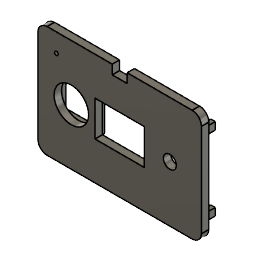
SLEEPHELPERCONFIG (Autodesk Fusion 360 archive; units mm, degrees)
design "SleepHelperFront"
part number: 2026-09-22-17-51-52-416
Autodesk Fusion 360 part; units mm, degrees
sketch "Sketch1" plane through (0, 0, 0) normal (0, 0, 1) x (1, 0, 0)
  line L0 (0, 0) -> (88, 0)
  line L1 (88, 0) -> (88, 60)
  line L2 (88, 60) -> (0, 60)
  line L3 (0, 60) -> (0, 0)
  dimension "d1" = 88
  dimension "d2" = 60
  constraint horizontal L0
  constraint vertical L1
  constraint horizontal L2
  constraint vertical L3
  constraint coincident L0.start L3.end
  measures "d1" distance of L0.start L0.end
  measures "d2" distance of L0.start L2.end
extrude "Extrude1" add sketch "Sketch1" along normal blind 4
fillet "Fillet1" radius 5 4 edges at (0, 60, 2) (88, 60, 2) (88, 0, 2) (0, 0, 2)
sketch "Sketch2" plane through (0, 0, 4) normal (0, 0, 1) x (1, 0, 0)
  arc A0 (0, 5) -> (5, 0) centre (5, 5) ccw
  line L0 (5, 0) -> (83, 0)
  arc A1 (83, 0) -> (88, 5) centre (83, 5) ccw
  line L1 (88, 5) -> (88, 55)
  arc A2 (88, 55) -> (83, 60) centre (83, 55) ccw
  line L2 (83, 60) -> (5, 60)
  arc A3 (5, 60) -> (0, 55) centre (5, 55) ccw
  line L3 (0, 55) -> (0, 5)
  line L4 (0, 30) -> (88, 30) construction
  circle A4 centre (18, 30) radius 9.25
  circle A5 centre (71, 30) radius 3.5
  line L5 (44, 60) -> (44, 0) construction
  line L6 (30.75, 20.5) -> (57.25, 20.5)
  line L7 (57.25, 20.5) -> (57.25, 39.5)
  line L8 (57.25, 39.5) -> (30.75, 39.5)
  line L9 (30.75, 39.5) -> (30.75, 20.5)
  circle A6 centre (71, 30) radius 10 construction
  line L10 (29.75, 41.5) -> (58.25, 41.5)
  line L11 (58.25, 41.5) -> (58.25, 18.5)
  line L12 (58.25, 18.5) -> (29.75, 18.5)
  line L13 (29.75, 18.5) -> (29.75, 41.5)
  line L14 (30.75, 39.5) -> (29.75, 39.5)
  line L15 (30.75, 20.5) -> (29.75, 20.5)
  dimension "d7" = 18.5
  dimension "d8" = 18
  dimension "d9" = 7
  dimension "d10" = 17
  dimension "d11" = 19
  dimension "d12" = 26.5
  dimension "d13" = 20.5
  dimension "d14" = 30.75
  dimension "d19" = 20
  dimension "d47" = 28.5
  dimension "d48" = 23
  dimension "d49" = 2
  dimension "d50" = 1
  constraint midpoint L3 L4.start
  constraint midpoint L1 L4.end
  constraint coincident L4 A4.centre
  constraint coincident L4 A5.centre
  constraint midpoint L2 L5.start
  constraint midpoint L0 L5.end
  constraint horizontal L6
  constraint vertical L7
  constraint horizontal L8
  constraint vertical L9
  constraint concentric A5 A6
  constraint horizontal L10
  constraint vertical L11
  constraint horizontal L12
  constraint vertical L13
  constraint coincident L13 L14.end
  constraint perpendicular L13 L14
  constraint coincident L13 L15.end
  constraint perpendicular L13 L15
  measures "d7" diameter of A4
  measures "d8" distance of L3 A4.centre
  measures "d9" diameter of A5
  measures "d10" distance of L1 A5.centre
  measures "d11" distance of L6.start L8.end
  measures "d12" distance of L6.start L6.end
  measures "d13" distance of L2 L8
  measures "d14" distance of L3 L9
  measures "d19" diameter of A6
  measures "d47" distance of L10.start L10.end
  measures "d48" distance of L10.start L12.end
  measures "d49" distance of L8 L10
  measures "d50" distance of L7 L11
extrude "Extrude2" cut sketch "Sketch2" against normal blind 5 contours A4 | A5 | L6 L7 L8 L9
sketch "Sketch6" plane through (0, 0, 0) normal (0, 0, -1) x (-1, 0, 0)
  line L0 (-30.75, 20.5) -> (-57.25, 20.5)
  line L1 (-57.25, 20.5) -> (-57.25, 39.5)
  line L2 (-57.25, 39.5) -> (-30.75, 39.5)
  line L3 (-30.75, 39.5) -> (-30.75, 20.5)
  circle A0 centre (-18, 30) radius 9.25
  circle A1 centre (-71, 30) radius 3.5
  arc A2 (-5, 0) -> (0, 5) centre (-5, 5) ccw
  line L4 (0, 5) -> (0, 55)
  arc A3 (0, 55) -> (-5, 60) centre (-5, 55) ccw
  line L5 (-5, 60) -> (-83, 60)
  arc A4 (-83, 60) -> (-88, 55) centre (-83, 55) ccw
  line L6 (-88, 55) -> (-88, 5)
  arc A5 (-88, 5) -> (-83, 0) centre (-83, 5) ccw
  line L7 (-83, 0) -> (-5, 0)
  line L8 (-58.25, 43.5) -> (-29.75, 43.5)
  line L9 (-29.75, 43.5) -> (-29.75, 16.5)
  line L10 (-29.75, 16.5) -> (-58.25, 16.5)
  line L11 (-58.25, 16.5) -> (-58.25, 43.5)
  line L12 (-27.75, 14.5) -> (-60.25, 14.5)
  line L13 (-60.25, 14.5) -> (-60.25, 45.5)
  line L14 (-60.25, 45.5) -> (-27.75, 45.5)
  line L15 (-27.75, 45.5) -> (-27.75, 14.5)
  dimension "d37" = 4
  dimension "d38" = 28.5
  dimension "d39" = 1
  dimension "d40" = 27
  dimension "d41" = -2
  constraint horizontal L8
  constraint vertical L9
  constraint horizontal L10
  constraint vertical L11
  measures "d37" distance of L2 L8
  measures "d38" distance of L9.end L10.end
  measures "d39" distance of L1 L11
  measures "d40" distance of L8.start L10.end
extrude "Extrude6" add sketch "Sketch6" along normal blind 3 contours L12 L13 L14 L15
sketch "Sketch7" plane through (0, 0, 0) normal (0, 0, -1) x (-1, 0, 0)
  arc A0 (-5, 0) -> (0, 5) centre (-5, 5) ccw
  line L0 (0, 5) -> (0, 55)
  arc A1 (0, 55) -> (-5, 60) centre (-5, 55) ccw
  line L1 (-5, 60) -> (-83, 60)
  arc A2 (-83, 60) -> (-88, 55) centre (-83, 55) ccw
  line L2 (-88, 55) -> (-88, 5)
  arc A3 (-88, 5) -> (-83, 0) centre (-83, 5) ccw
  line L3 (-83, 0) -> (-5, 0)
  circle A4 centre (-71, 30) radius 3.5
  circle A5 centre (-18, 30) radius 9.25
  line L4 (-27.75, 45.5) -> (-27.75, 14.5)
  line L5 (-27.75, 14.5) -> (-60.25, 14.5)
  line L6 (-60.25, 14.5) -> (-60.25, 45.5)
  line L7 (-60.25, 45.5) -> (-27.75, 45.5)
  line L8 (-28.125, 40) -> (-8.125, 40)
  line L9 (-8.125, 40) -> (-8.125, 20)
  line L10 (-8.125, 20) -> (-28.125, 20)
  line L11 (-28.125, 20) -> (-28.125, 40)
  line L12 (-6.875, 18.75) -> (-29.375, 18.75)
  line L13 (-29.375, 18.75) -> (-29.375, 41.25)
  line L14 (-29.375, 41.25) -> (-6.875, 41.25)
  line L15 (-6.875, 41.25) -> (-6.875, 18.75)
  dimension "d44" = -1.25
  dimension "d61" = 9.875
  constraint horizontal L8
  constraint vertical L9
  constraint horizontal L10
  constraint vertical L11
  measures "d61" distance of A5.centre L9
extrude "Extrude7" add sketch "Sketch7" along normal blind 3 contours L4 L8 L9 L10 L12 L14 L15 | L4 L8 L10 L11 L12 L13 L14
sketch "Sketch9" plane through (0, 0, 4) normal (0, 0, 1) x (1, 0, 0)
  line L0 (57.25, 20.5) -> (30.75, 20.5)
  line L1 (30.75, 20.5) -> (30.75, 39.5)
  line L2 (30.75, 39.5) -> (57.25, 39.5)
  line L3 (57.25, 39.5) -> (57.25, 20.5)
  circle A0 centre (18, 30) radius 9.25
  circle A1 centre (71, 30) radius 3.5
  arc A2 (0, 5) -> (5, 0) centre (5, 5) ccw
  line L4 (5, 0) -> (83, 0)
  arc A3 (83, 0) -> (88, 5) centre (83, 5) ccw
  line L5 (88, 5) -> (88, 55)
  arc A4 (88, 55) -> (83, 60) centre (83, 55) ccw
  line L6 (83, 60) -> (5, 60)
  arc A5 (5, 60) -> (0, 55) centre (5, 55) ccw
  line L7 (0, 55) -> (0, 5)
  circle A6 centre (10, 50) radius 1
  dimension "d54" = 2
  measures "d54" diameter of A6
extrude "Extrude9" cut sketch "Sketch9" against normal blind 21 contours A6
sketch "Sketch10" plane through (0, 60, 0) normal (0, 1, 0) x (-1, 0, 0)
  line L0 (-83, 4) -> (-83, 0)
  line L1 (-83, 0) -> (-5, 0)
  line L2 (-5, 0) -> (-5, 4)
  line L3 (-5, 4) -> (-83, 4)
  line L4 (-40, 0) -> (-48, 0)
  line L5 (-48, 0) -> (-48, 4)
  line L6 (-48, 4) -> (-40, 4)
  line L7 (-40, 4) -> (-40, 0)
  dimension "d57" = 8
  dimension "d58" = 35
  constraint horizontal L4
  constraint vertical L5
  constraint horizontal L6
  constraint vertical L7
  constraint coincident L1 L4.start
  measures "d57" distance of L4.start L4.end
  measures "d58" distance of L2 L7
extrude "Extrude10" cut sketch "Sketch10" against normal blind 5 contours L1 L3 L4 L5 L6 L7
sketch "Sketch11" plane through (0, 0, -3) normal (0, 0, -1) x (-1, 0, 0)
  line L0 (-27.75, 20) -> (-27.75, 40)
  line L1 (-27.75, 40) -> (-8.125, 40)
  line L2 (-8.125, 40) -> (-8.125, 20)
  line L3 (-8.125, 20) -> (-27.75, 20)
  line L4 (-29.75, 16.5) -> (-58.25, 16.5)
  line L5 (-58.25, 16.5) -> (-58.25, 43.5)
  line L6 (-58.25, 43.5) -> (-29.75, 43.5)
  line L7 (-29.75, 43.5) -> (-29.75, 16.5)
  line L8 (-27.75, 18.75) -> (-6.875, 18.75)
  line L9 (-6.875, 18.75) -> (-6.875, 41.25)
  line L10 (-6.875, 41.25) -> (-27.75, 41.25)
  line L11 (-27.75, 41.25) -> (-27.75, 45.5)
  line L12 (-27.75, 45.5) -> (-60.25, 45.5)
  line L13 (-60.25, 45.5) -> (-60.25, 14.5)
  line L14 (-60.25, 14.5) -> (-27.75, 14.5)
  line L15 (-27.75, 14.5) -> (-27.75, 18.75)
  line L16 (-29.75, 16.5) -> (-27.75, 16.5)
  line L17 (-27.75, 18.75) -> (-29.75, 18.75)
  line L18 (-29.75, 18.75) -> (-29.75, 16.5)
  line L19 (-27.75, 16.5) -> (-27.75, 18.75)
  line L20 (-29.75, 43.5) -> (-27.75, 43.5)
  line L21 (-27.75, 43.5) -> (-27.75, 41.25)
  line L22 (-27.75, 41.25) -> (-29.75, 41.25)
  line L23 (-29.75, 41.25) -> (-29.75, 43.5)
  constraint coincident L4.start L7.end
  constraint coincident L15 L16.end
  constraint perpendicular L15 L16
  constraint coincident L8.start L15.end
  constraint coincident L7 L17.end
  constraint perpendicular L7 L17
  constraint horizontal L20
  constraint vertical L21
  constraint horizontal L22
  constraint vertical L23
  constraint coincident L10.end L11.start
  constraint coincident L6.end L7.start
extrude "Extrude11" cut sketch "Sketch11" against normal blind 3 contours L7 L15 L16 L17 L18 L19 | L7 L11 L20 L21 L22 L23
sketch "Sketch12" plane through (0, 0, -3) normal (0, 0, -1) x (-1, 0, 0)
  line L0 (-29.75, 18.75) -> (-6.875, 18.75)
  line L1 (-6.875, 18.75) -> (-6.875, 41.25)
  line L2 (-6.875, 41.25) -> (-29.75, 41.25)
  line L3 (-29.75, 41.25) -> (-29.75, 18.75)
  line L4 (-27.75, 20) -> (-27.75, 40)
  line L5 (-27.75, 40) -> (-8.125, 40)
  line L6 (-8.125, 40) -> (-8.125, 20)
  line L7 (-8.125, 20) -> (-27.75, 20)
  line L8 (-29, 41.25) -> (-29, 18.75)
  dimension "d64" = 1.25
  constraint coincident L2 L8.start
  constraint coincident L0 L8.end
  constraint perpendicular L0 L8
  measures "d64" distance of L4 L8
extrude "Extrude12" cut sketch "Sketch12" against normal blind 3 contours L0 L2 L3 L8
sketch "Sketch13" plane through (0, 0, 0) normal (0, 0, -1) x (-1, 0, 0)
  line L0 (-29, 41.25) -> (-6.875, 41.25)
  line L1 (-6.875, 41.25) -> (-6.875, 18.75)
  line L2 (-6.875, 18.75) -> (-29, 18.75)
  line L3 (-29, 18.75) -> (-29, 41.25)
  line L4 (-30.75, 20.5) -> (-57.25, 20.5)
  line L5 (-57.25, 20.5) -> (-57.25, 39.5)
  line L6 (-57.25, 39.5) -> (-30.75, 39.5)
  line L7 (-30.75, 39.5) -> (-30.75, 20.5)
  line L8 (-48, 55) -> (-48, 60)
  line L9 (-48, 60) -> (-83, 60)
  arc A0 (-83, 60) -> (-88, 55) centre (-83, 55) ccw
  line L10 (-88, 55) -> (-88, 5)
  arc A1 (-88, 5) -> (-83, 0) centre (-83, 5) ccw
  line L11 (-83, 0) -> (-5, 0)
  arc A2 (-5, 0) -> (0, 5) centre (-5, 5) ccw
  line L12 (0, 5) -> (0, 55)
  arc A3 (0, 55) -> (-5, 60) centre (-5, 55) ccw
  line L13 (-5, 60) -> (-40, 60)
  line L14 (-40, 60) -> (-40, 55)
  line L15 (-40, 55) -> (-48, 55)
  circle A4 centre (-10, 50) radius 1
  line L16 (-58.25, 16.5) -> (-27.75, 16.5)
  line L17 (-27.75, 16.5) -> (-27.75, 14.5)
  line L18 (-27.75, 14.5) -> (-60.25, 14.5)
  line L19 (-60.25, 14.5) -> (-60.25, 45.5)
  line L20 (-60.25, 45.5) -> (-27.75, 45.5)
  line L21 (-27.75, 45.5) -> (-27.75, 43.5)
  line L22 (-27.75, 43.5) -> (-58.25, 43.5)
  line L23 (-58.25, 43.5) -> (-58.25, 16.5)
  circle A5 centre (-71, 30) radius 3.5
  line L24 (-86.5, 52) -> (-84, 52)
  line L25 (-84, 52) -> (-84, 48)
  line L26 (-84, 48) -> (-86.5, 48)
  line L27 (-86.5, 48) -> (-86.5, 52)
  line L28 (-86.5, 12) -> (-84, 12)
  line L29 (-84, 12) -> (-84, 8)
  line L30 (-84, 8) -> (-86.5, 8)
  line L31 (-86.5, 8) -> (-86.5, 12)
  line L32 (-44, 0) -> (-44, 55) construction
  line L33 (-1.5, 52) -> (-4, 52)
  line L34 (-4, 52) -> (-4, 48)
  line L35 (-4, 48) -> (-1.5, 48)
  line L36 (-1.5, 48) -> (-1.5, 52)
  line L37 (-4, 12) -> (-4, 8)
  line L38 (-1.5, 12) -> (-4, 12)
  line L39 (-1.5, 8) -> (-1.5, 12)
  line L40 (-4, 8) -> (-1.5, 8)
  dimension "d67" = 2.5
  dimension "d68" = 4
  dimension "d69" = 2.5
  dimension "d70" = 4
  dimension "d71" = 1.5
  dimension "d72" = 8
  dimension "d73" = 1.5
  dimension "d74" = 8
  constraint horizontal L24
  constraint vertical L25
  constraint horizontal L26
  constraint vertical L27
  constraint horizontal L28
  constraint vertical L29
  constraint horizontal L30
  constraint vertical L31
  constraint midpoint L11 L32.start
  constraint midpoint L15 L32.end
  constraint symmetric L24.start L32 L33.start
  constraint symmetric L24.end L32 L33.end
  constraint symmetric L25.end L32 L34.end
  constraint symmetric L26.end L32 L35.end
  constraint symmetric L28.start L32 L38.start
  constraint symmetric L28.end L32 L37.start
  constraint symmetric L29.end L32 L37.end
  constraint symmetric L30.end L32 L39.start
  measures "d67" distance of L24.start L24.end
  measures "d68" distance of L24.start L26.end
  measures "d69" distance of L28.start L28.end
  measures "d70" distance of L28.start L30.end
  measures "d71" distance of L10 L27
  measures "d72" distance of L9.end L24
  measures "d73" distance of L10 L28.start
  measures "d74" vertical distance of A1.end L29.end
extrude "Extrude13" add sketch "Sketch13" along normal blind 5 contours L24 L25 L26 L27 | L28 L29 L30 L31 | L33 L34 L35 L36 | L37 L38 L39 L40
equation "d12 = 27.5 mm - 1 mm"
equation "d13 = ( ( 60 - 19 ) / 2 ) * 1 mm"
equation "d14 = ( ( ( 88 - 27.5 ) / 2 ) * 1 mm ) + 0.5 * 1 mm"
equation "d48 = 19 mm + 4 mm"
equation "d61 = ( 19.75 / 2 ) * 1 mm"

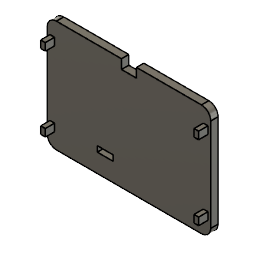
design "SleepHelperBack"
part number: 2026-09-24-13-16-22-651
Autodesk Fusion 360 part; units mm, degrees
sketch "Sketch1" plane through (0, 0, 0) normal (0, 0, 1) x (1, 0, 0)
  line L0 (0, 0) -> (-88, 0)
  line L1 (-88, 0) -> (-88, 60)
  line L2 (-88, 60) -> (0, 60)
  line L3 (0, 60) -> (0, 0)
  dimension "d1" = 88
  dimension "d2" = 60
  constraint horizontal L0
  constraint vertical L1
  constraint horizontal L2
  constraint vertical L3
  constraint coincident L0.start L3.end
  measures "d1" distance of L0.start L0.end
  measures "d2" distance of L0.start L2.end
extrude "Extrude1" add sketch "Sketch1" along normal blind 4
fillet "Fillet1" radius 5 4 edges at (0, 60, 2) (-88, 60, 2) (0, 0, 2) (-88, 0, 2)
sketch "Sketch2" plane through (0, 0, 0) normal (0, 0, -1) x (-1, 0, 0)
  arc A0 (83, 0) -> (88, 5) centre (83, 5) ccw
  line L0 (88, 5) -> (88, 55)
  arc A1 (88, 55) -> (83, 60) centre (83, 55) ccw
  line L1 (83, 60) -> (5, 60)
  arc A2 (5, 60) -> (0, 55) centre (5, 55) ccw
  line L2 (0, 55) -> (0, 5)
  arc A3 (0, 5) -> (5, 0) centre (5, 5) ccw
  line L3 (5, 0) -> (83, 0)
  line L4 (83, 60) -> (83, 0) construction
  line L5 (52.5, 13) -> (61, 13)
  line L6 (61, 13) -> (61, 10)
  line L7 (61, 10) -> (52.5, 10)
  line L8 (52.5, 10) -> (52.5, 13)
  dimension "d7" = 8.5
  dimension "d8" = 3
  dimension "d9" = 22
  dimension "d10" = 10
  constraint coincident A1.end L1.start
  constraint coincident A0.start L3.end
  constraint horizontal L5
  constraint vertical L6
  constraint horizontal L7
  constraint vertical L8
  measures "d7" distance of L5.start L5.end
  measures "d8" distance of L5.start L7.end
  measures "d9" distance of L4 L6
  measures "d10" distance of L3 L7
extrude "Extrude2" cut sketch "Sketch2" against normal blind 35 contours L5 L6 L7 L8
sketch "Sketch4" plane through (0, 60, 0) normal (0, 1, 0) x (-1, 0, 0)
  line L0 (83, 0) -> (83, 4)
  line L1 (83, 4) -> (5, 4)
  line L2 (5, 4) -> (5, 0)
  line L3 (5, 0) -> (83, 0)
  line L4 (40, 4) -> (48, 4)
  line L5 (48, 4) -> (48, 0)
  line L6 (48, 0) -> (40, 0)
  line L7 (40, 0) -> (40, 4)
  dimension "d18" = 8
  dimension "d19" = 4
  dimension "d20" = 35
  constraint horizontal L4
  constraint vertical L5
  constraint horizontal L6
  constraint vertical L7
  constraint coincident L1 L4.start
  measures "d18" distance of L4.start L4.end
  measures "d19" distance of L4.start L6.end
  measures "d20" distance of L2.end L7
extrude "Extrude4" cut sketch "Sketch4" against normal blind 5 contours L1 L3 L4 L5 L6 L7
sketch "Sketch5" plane through (0, 0, 4) normal (0, 0, 1) x (1, 0, 0)
  line L0 (-40, 60) -> (-40, 55)
  line L1 (-40, 55) -> (-48, 55)
  line L2 (-48, 55) -> (-48, 60)
  line L3 (-48, 60) -> (-83, 60)
  arc A0 (-83, 60) -> (-88, 55) centre (-83, 55) ccw
  line L4 (-88, 55) -> (-88, 5)
  arc A1 (-88, 5) -> (-83, 0) centre (-83, 5) ccw
  line L5 (-83, 0) -> (-5, 0)
  arc A2 (-5, 0) -> (0, 5) centre (-5, 5) ccw
  line L6 (0, 5) -> (0, 55)
  arc A3 (0, 55) -> (-5, 60) centre (-5, 55) ccw
  line L7 (-5, 60) -> (-40, 60)
  line L8 (-61, 10) -> (-61, 13)
  line L9 (-61, 13) -> (-52.5, 13)
  line L10 (-52.5, 13) -> (-52.5, 10)
  line L11 (-52.5, 10) -> (-61, 10)
  line L12 (-86.5, 52) -> (-84, 52)
  line L13 (-84, 52) -> (-84, 48)
  line L14 (-84, 48) -> (-86.5, 48)
  line L15 (-86.5, 48) -> (-86.5, 52)
  line L16 (-86.5, 12) -> (-84, 12)
  line L17 (-84, 12) -> (-84, 8)
  line L18 (-84, 8) -> (-86.5, 8)
  line L19 (-86.5, 8) -> (-86.5, 12)
  line L20 (-44, 55) -> (-44, 0) construction
  line L21 (-4, 52) -> (-4, 48)
  line L22 (-4, 48) -> (-1.5, 48)
  line L23 (-1.5, 48) -> (-1.5, 52)
  line L24 (-1.5, 52) -> (-4, 52)
  line L25 (-1.5, 12) -> (-4, 12)
  line L26 (-1.5, 8) -> (-1.5, 12)
  line L27 (-4, 8) -> (-1.5, 8)
  line L28 (-4, 12) -> (-4, 8)
  dimension "d23" = 2.5
  dimension "d24" = 4
  dimension "d25" = 1.5
  dimension "d26" = 8
  dimension "d27" = 1.5
  dimension "d28" = 8
  dimension "d31" = 4
  dimension "d32" = 2.5
  constraint horizontal L12
  constraint vertical L13
  constraint horizontal L14
  constraint vertical L15
  constraint horizontal L16
  constraint vertical L17
  constraint horizontal L18
  constraint vertical L19
  constraint midpoint L1 L20.start
  constraint midpoint L5 L20.end
  constraint symmetric L12.start L20 L23.end
  constraint symmetric L12.end L20 L21.start
  constraint symmetric L13.end L20 L21.end
  constraint symmetric L14.end L20 L22.end
  constraint symmetric L16.start L20 L25.start
  constraint symmetric L16.end L20 L25.end
  constraint symmetric L17.end L20 L27.start
  constraint symmetric L18.end L20 L26.start
  measures "d23" distance of L12.start L12.end
  measures "d24" distance of L12.start L14.end
  measures "d25" distance of L4 L15
  measures "d26" vertical distance of L3.end L12.end
  measures "d27" distance of L4 L19
  measures "d28" vertical distance of A1.end L17.end
  measures "d31" distance of L16.end L17.end
  measures "d32" distance of L17.end L18.end
extrude "Extrude5" add sketch "Sketch5" along normal blind 5 contours L12 L13 L14 L15 | L16 L17 L18 L19 | L21 L22 L23 L24 | L25 L26 L27 L28

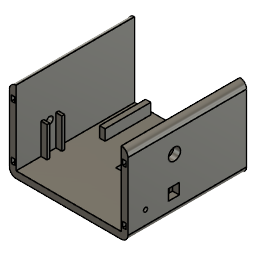
design "SidePieceSleepHelper"
part number: 2026-09-24-13-18-35-575
Autodesk Fusion 360 part; units mm, degrees
sketch "Sketch1" plane through (0, 0, 0) normal (0, 0, 1) x (1, 0, 0)
  line L0 (0, 0) -> (88, 0)
  line L1 (88, 0) -> (88, 60)
  line L2 (88, 60) -> (0, 60)
  line L3 (0, 60) -> (0, 0)
  dimension "d11" = 88
  dimension "d12" = 60
  constraint horizontal L0
  constraint vertical L1
  constraint horizontal L2
  constraint vertical L3
  constraint coincident L0.start L3.end
  measures "d11" distance of L0.start L0.end
  measures "d12" distance of L0.start L2.end
extrude "Extrude2" add sketch "Sketch1" along normal blind 88
fillet "Fillet2" radius 5 4 edges at (88, 60, 44) (0, 60, 44) (88, 0, 44) (0, 0, 44)
sketch "Sketch2" plane through (0, 0, 88) normal (0, 0, 1) x (1, 0, 0)
  arc A0 (0, 5) -> (5, 0) centre (5, 5) ccw
  line L0 (5, 0) -> (83, 0)
  arc A1 (83, 0) -> (88, 5) centre (83, 5) ccw
  line L1 (88, 5) -> (88, 55)
  arc A2 (88, 55) -> (83, 60) centre (83, 55) ccw
  line L2 (83, 60) -> (5, 60)
  arc A3 (5, 60) -> (0, 55) centre (5, 55) ccw
  line L3 (0, 55) -> (0, 5)
  line L4 (5, 55) -> (83, 55)
  line L5 (83, 55) -> (83, 5)
  line L6 (83, 5) -> (5, 5)
  line L7 (5, 5) -> (5, 55)
  constraint horizontal L4
  constraint vertical L5
  constraint horizontal L6
  constraint vertical L7
  constraint coincident A1.centre L5.end
  constraint coincident A3.centre L4.start
extrude "Extrude3" cut sketch "Sketch2" against normal blind 145 contours L4 L5 L6 L7
sketch "Sketch3" plane through (0, 0, 88) normal (0, 0, 1) x (1, 0, 0)
  line L0 (83, 55) -> (83, 5)
  line L1 (83, 5) -> (5, 5)
  line L2 (5, 5) -> (5, 55)
  line L3 (5, 55) -> (83, 55)
  arc A0 (0, 5) -> (5, 0) centre (5, 5) ccw
  line L4 (5, 0) -> (83, 0)
  arc A1 (83, 0) -> (88, 5) centre (83, 5) ccw
  line L5 (88, 5) -> (88, 55)
  arc A2 (88, 55) -> (83, 60) centre (83, 55) ccw
  line L6 (83, 60) -> (5, 60)
  arc A3 (5, 60) -> (0, 55) centre (5, 55) ccw
  line L7 (0, 55) -> (0, 5)
  line L8 (5, 60) -> (83, 60)
  line L9 (83, 60) -> (83, 55)
  line L10 (83, 55) -> (5, 55)
  line L11 (5, 55) -> (5, 60)
  constraint horizontal L8
  constraint vertical L9
  constraint horizontal L10
  constraint vertical L11
  constraint coincident L0.start L3.end
  constraint coincident L6.end A3.start
extrude "Extrude4" cut sketch "Sketch3" against normal blind 130 contours L3 L6 L8 L9 L10 L11
sketch "Sketch4" plane through (0, 0, 0) normal (-1, 0, 0) x (0, 0, 1)
  line L0 (0, 5) -> (88, 5)
  line L1 (88, 5) -> (88, 55)
  line L2 (88, 55) -> (0, 55)
  line L3 (0, 55) -> (0, 5)
  circle A0 centre (63, 25) radius 2.5
  dimension "d21" = 25
  dimension "d22" = 20
  dimension "d25" = 5
  measures "d21" distance of L1 A0.centre
  measures "d22" distance of L0 A0.centre
  measures "d25" diameter of A0
extrude "Extrude5" cut sketch "Sketch4" against normal blind 12 contours A0
sketch "Sketch5" plane through (88, 0, 0) normal (1, 0, 0) x (0, 0, -1)
  line L0 (-88, 5) -> (0, 5)
  line L1 (0, 5) -> (0, 55)
  line L2 (0, 55) -> (-88, 55)
  line L3 (-88, 55) -> (-88, 5)
  line L4 (-58, 20) -> (-50, 20)
  line L5 (-50, 20) -> (-50, 12)
  line L6 (-50, 12) -> (-58, 12)
  line L7 (-58, 12) -> (-58, 20)
  dimension "d26" = 8
  dimension "d27" = 8
  dimension "d28" = 7
  dimension "d29" = 30
  constraint horizontal L4
  constraint vertical L5
  constraint horizontal L6
  constraint vertical L7
  measures "d26" distance of L4.start L4.end
  measures "d27" distance of L4.start L6.end
  measures "d28" distance of L0 L6
  measures "d29" distance of L3 L7
extrude "Extrude6" cut sketch "Sketch5" against normal blind 35 contours L4 L5 L6 L7
sketch "Sketch6" plane through (0, 5, 0) normal (0, 1, 0) x (-1, 0, 0)
  line L0 (-83, 0) -> (-5, 0)
  line L1 (-5, 0) -> (-5, 88)
  line L2 (-5, 88) -> (-83, 88)
  line L3 (-83, 88) -> (-83, 0)
  line L4 (-15, 2) -> (-19, 2)
  line L5 (-19, 2) -> (-19, 36)
  line L6 (-19, 36) -> (-15, 36)
  line L7 (-15, 36) -> (-15, 2)
  line L8 (-41, 2) -> (-44, 2)
  line L9 (-44, 2) -> (-44, 36)
  line L10 (-44, 36) -> (-41, 36)
  line L11 (-41, 36) -> (-41, 2)
  dimension "d36" = 34
  dimension "d37" = 22
  dimension "d38" = 10
  dimension "d41" = 2
  constraint horizontal L4
  constraint vertical L5
  constraint horizontal L6
  constraint vertical L7
  constraint horizontal L8
  constraint vertical L9
  constraint horizontal L10
  constraint vertical L11
  measures "d36" distance of L4.start L6.end
  measures "d37" distance of L5 L11
  measures "d38" distance of L1 L7
  measures "d41" distance of L0 L4
extrude "Extrude7" add sketch "Sketch6" along normal blind 8 contours L4 L5 L6 L7 | L8 L9 L10 L11
sketch "Sketch7" plane through (88, 0, 0) normal (1, 0, 0) x (0, 0, -1)
  line L0 (-50, 20) -> (-50, 12)
  line L1 (-50, 12) -> (-58, 12)
  line L2 (-58, 12) -> (-58, 20)
  line L3 (-58, 20) -> (-50, 20)
  line L4 (-88, 5) -> (0, 5)
  line L5 (0, 5) -> (0, 55)
  line L6 (0, 55) -> (-88, 55)
  line L7 (-88, 55) -> (-88, 5)
  circle A0 centre (-75, 15) radius 1.5
  dimension "d42" = 3
  measures "d42" diameter of A0
extrude "Extrude8" cut sketch "Sketch7" against normal blind 41 contours A0
sketch "Sketch8" plane through (83, 0, 0) normal (-1, 0, 0) x (0, 0, 1)
  circle A0 centre (75, 15) radius 1.5
  line L0 (50, 12) -> (50, 20)
  line L1 (50, 20) -> (58, 20)
  line L2 (58, 20) -> (58, 12)
  line L3 (58, 12) -> (50, 12)
  line L4 (0, 60) -> (0, 5)
  line L5 (0, 5) -> (88, 5)
  line L6 (88, 5) -> (88, 60)
  line L7 (88, 60) -> (0, 60)
  line L8 (59.5, 20) -> (61.5, 20)
  line L9 (61.5, 20) -> (61.5, 12)
  line L10 (59.5, 12) -> (59.5, 20)
  line L11 (48.5, 20) -> (46.5, 20)
  line L12 (46.5, 20) -> (46.5, 12)
  line L13 (48.5, 12) -> (48.5, 20)
  line L14 (59.5, 12) -> (59.5, 5)
  line L15 (61.5, 12) -> (61.5, 5)
  line L16 (46.5, 12) -> (46.5, 5)
  line L17 (48.5, 12) -> (48.5, 5)
  line L18 (46.5, 5) -> (48.5, 5)
  line L19 (59.5, 5) -> (61.5, 5)
  dimension "d45" = 2
  dimension "d46" = 2
  dimension "d47" = 8
  dimension "d48" = 1.5
  dimension "d49" = 1.5
  constraint horizontal L8
  constraint vertical L9
  constraint vertical L10
  constraint horizontal L11
  constraint vertical L12
  constraint vertical L13
  constraint coincident L5 L14.end
  constraint perpendicular L5 L14
  constraint coincident L5 L15.end
  constraint perpendicular L5 L15
  constraint coincident L5 L16.end
  constraint perpendicular L5 L16
  constraint coincident L5 L17.end
  constraint perpendicular L5 L17
  measures "d45" distance of L8.start L8.end
  measures "d46" distance of L11.start L11.end
  measures "d47" distance of L11.start L13.start
  measures "d48" distance of L0 L13
  measures "d49" distance of L2.end L10.start
extrude "Extrude9" add sketch "Sketch8" along normal blind 4 contours L5 L11 L12 L13 L16 L17 L18 | L5 L8 L9 L10 L14 L15 L19
sketch "Sketch9" plane through (5, 0, 0) normal (1, 0, 0) x (0, 0, -1)
  circle A0 centre (-63, 25) radius 2.5
  line L0 (0, 5) -> (0, 60)
  line L1 (0, 60) -> (-88, 60)
  line L2 (-88, 60) -> (-88, 5)
  line L3 (-88, 5) -> (0, 5)
  line L4 (-69.5, 27.6793) -> (-67.5, 27.6793)
  line L5 (-67.5, 27.6793) -> (-67.5, 13.6793)
  line L6 (-69.5, 13.6793) -> (-69.5, 27.6793)
  line L7 (-58.5, 27.6793) -> (-56.5, 27.6793)
  line L8 (-56.5, 27.6793) -> (-56.5, 13.6793)
  line L9 (-58.5, 13.6793) -> (-58.5, 27.6793)
  line L10 (-69.5, 13.6793) -> (-69.5, 5)
  line L11 (-67.5, 13.6793) -> (-67.5, 5)
  line L12 (-69.5, 5) -> (-67.5, 5)
  line L13 (-58.5, 13.6793) -> (-58.5, 5)
  line L14 (-56.5, 13.6793) -> (-56.5, 5)
  line L15 (-58.5, 5) -> (-56.5, 5)
  dimension "d52" = 2
  dimension "d53" = 14
  dimension "d54" = 2
  dimension "d55" = 4.5
  dimension "d56" = 4.5
  constraint horizontal L4
  constraint vertical L5
  constraint vertical L6
  constraint horizontal L7
  constraint vertical L8
  constraint vertical L9
  constraint coincident L3 L10.end
  constraint perpendicular L3 L10
  constraint coincident L3 L11.end
  constraint perpendicular L3 L11
  constraint coincident L3 L13.end
  constraint perpendicular L3 L13
  constraint coincident L3 L14.end
  constraint perpendicular L3 L14
  measures "d52" distance of L4.start L4.end
  measures "d53" distance of L4.start L6.start
  measures "d54" distance of L7.start L7.end
  measures "d55" distance of A0.centre L9
  measures "d56" distance of A0.centre L5
extrude "Extrude10" add sketch "Sketch9" along normal blind 4.5 contours L3 L7 L8 L9 L13 L14 L15 | L3 L4 L5 L6 L10 L11 L12
sketch "Sketch10" plane through (0, 5, 0) normal (0, 1, 0) x (-1, 0, 0)
  line L0 (-41, 36) -> (-41, 2)
  line L1 (-41, 2) -> (-44, 2)
  line L2 (-44, 2) -> (-44, 36)
  line L3 (-44, 36) -> (-41, 36)
  line L4 (-15, 36) -> (-15, 2)
  line L5 (-15, 2) -> (-19, 2)
  line L6 (-19, 2) -> (-19, 36)
  line L7 (-19, 36) -> (-15, 36)
  line L8 (-83, 0) -> (-5, 0)
  line L9 (-5, 58.5) -> (-5, 67.5)
  line L10 (-5, 88) -> (-83, 88)
  line L11 (-83, 88) -> (-83, 61.5)
  line L12 (-40, 39) -> (-50, 39)
  line L13 (-50, 39) -> (-50, 49)
  line L14 (-50, 49) -> (-40, 49)
  line L15 (-40, 49) -> (-40, 39)
  line L16 (-9.5, 58.5) -> (-5, 58.5)
  line L17 (-5, 67.5) -> (-9.5, 67.5)
  line L18 (-9.5, 67.5) -> (-9.5, 69.5)
  line L19 (-9.5, 69.5) -> (-5, 69.5)
  line L20 (-5, 69.5) -> (-5, 88)
  line L21 (-5, 0) -> (-5, 56.5)
  line L22 (-5, 56.5) -> (-9.5, 56.5)
  line L23 (-9.5, 56.5) -> (-9.5, 58.5)
  line L24 (-83, 61.5) -> (-79, 61.5)
  line L25 (-79, 61.5) -> (-79, 59.5)
  line L26 (-79, 59.5) -> (-83, 59.5)
  line L27 (-83, 59.5) -> (-83, 48.5)
  line L28 (-83, 48.5) -> (-79, 48.5)
  line L29 (-79, 48.5) -> (-79, 46.5)
  line L30 (-79, 46.5) -> (-83, 46.5)
  line L31 (-83, 46.5) -> (-83, 0)
  dimension "d59" = 39
  constraint horizontal L12
  constraint vertical L13
  constraint horizontal L14
  constraint vertical L15
  measures "d59" distance of L8 L12
extrude "Extrude11" cut sketch "Sketch10" against normal blind 35 contours L12 L13 L14 L15
sketch "Sketch11" plane through (88, 0, 0) normal (1, 0, 0) x (0, 0, -1)
  circle A0 centre (-75, 15) radius 1.5
  line L0 (-50, 20) -> (-50, 12)
  line L1 (-50, 12) -> (-58, 12)
  line L2 (-58, 12) -> (-58, 20)
  line L3 (-58, 20) -> (-50, 20)
  line L4 (-88, 5) -> (0, 5)
  line L5 (0, 5) -> (0, 55)
  line L6 (0, 55) -> (-88, 55)
  line L7 (-88, 55) -> (-88, 5)
  circle A1 centre (-53.5, 40) radius 4.5
  dimension "d62" = 9
  dimension "d65" = 34.5
  measures "d62" diameter of A1
  measures "d65" distance of L7 A1.centre
extrude "Extrude12" cut sketch "Sketch11" against normal blind 10 contours A1
sketch "Sketch12" plane through (0, 0, 88) normal (0, 0, 1) x (1, 0, 0)
  line L0 (83, 60) -> (83, 5)
  line L1 (83, 5) -> (5, 5)
  line L2 (5, 5) -> (5, 60)
  arc A0 (5, 60) -> (0, 55) centre (5, 55) ccw
  line L3 (0, 55) -> (0, 5)
  arc A1 (0, 5) -> (5, 0) centre (5, 5) ccw
  line L4 (5, 0) -> (83, 0)
  arc A2 (83, 0) -> (88, 5) centre (83, 5) ccw
  line L5 (88, 5) -> (88, 55)
  arc A3 (88, 55) -> (83, 60) centre (83, 55) ccw
  line L6 (1.5, 52) -> (4, 52)
  line L7 (4, 52) -> (4, 48)
  line L8 (4, 48) -> (1.5, 48)
  line L9 (1.5, 48) -> (1.5, 52)
  line L10 (1.5, 12) -> (4, 12)
  line L11 (4, 12) -> (4, 8)
  line L12 (4, 8) -> (1.5, 8)
  line L13 (1.5, 8) -> (1.5, 12)
  line L14 (44, 0) -> (44, 60) construction
  line L15 (86.5, 52) -> (84, 52)
  line L16 (86.5, 48) -> (86.5, 52)
  line L17 (84, 48) -> (86.5, 48)
  line L18 (84, 52) -> (84, 48)
  line L19 (86.5, 8) -> (86.5, 12)
  line L20 (84, 8) -> (86.5, 8)
  line L21 (84, 12) -> (84, 8)
  line L22 (86.5, 12) -> (84, 12)
  dimension "d66" = 2.5
  dimension "d67" = 4
  dimension "d68" = 8
  dimension "d69" = 1.5
  dimension "d70" = 2.5
  dimension "d71" = 4
  dimension "d72" = 8
  dimension "d73" = 1.5
  constraint horizontal L6
  constraint vertical L7
  constraint horizontal L8
  constraint vertical L9
  constraint horizontal L10
  constraint vertical L11
  constraint horizontal L12
  constraint vertical L13
  constraint midpoint L4 L14.start
  constraint perpendicular L4 L14
  constraint symmetric L6.start L14 L15.start
  constraint symmetric L6.end L14 L15.end
  constraint symmetric L7.end L14 L17.start
  constraint symmetric L8.end L14 L16.start
  constraint symmetric L10.start L14 L19.end
  constraint symmetric L10.end L14 L21.start
  constraint symmetric L11.end L14 L20.start
  constraint symmetric L12.end L14 L19.start
  measures "d66" distance of L6.start L6.end
  measures "d67" distance of L6.start L8.end
  measures "d68" vertical distance of L2.end L6.end
  measures "d69" distance of L3 L8.end
  measures "d70" distance of L10.start L10.end
  measures "d71" distance of L10.start L12.end
  measures "d72" vertical distance of A1.end L11.end
  measures "d73" distance of L3 L12.end
extrude "Extrude13" cut sketch "Sketch12" against normal blind 5 contours L6 L7 L8 L9 | L10 L11 L12 L13 | L15 L16 L17 L18 | L19 L20 L21 L22
sketch "Sketch13" plane through (0, 0, 0) normal (0, 0, -1) x (-1, 0, 0)
  line L0 (-83, 5) -> (-83, 60)
  arc A0 (-83, 60) -> (-88, 55) centre (-83, 55) ccw
  line L1 (-88, 55) -> (-88, 5)
  arc A1 (-88, 5) -> (-83, 0) centre (-83, 5) ccw
  line L2 (-83, 0) -> (-5, 0)
  arc A2 (-5, 0) -> (0, 5) centre (-5, 5) ccw
  line L3 (0, 5) -> (0, 55)
  arc A3 (0, 55) -> (-5, 60) centre (-5, 55) ccw
  line L4 (-5, 60) -> (-5, 5)
  line L5 (-5, 5) -> (-83, 5)
  line L6 (-86.5, 52) -> (-84, 52)
  line L7 (-84, 52) -> (-84, 48)
  line L8 (-84, 48) -> (-86.5, 48)
  line L9 (-86.5, 48) -> (-86.5, 52)
  line L10 (-86.5, 12) -> (-84, 12)
  line L11 (-84, 12) -> (-84, 8)
  line L12 (-84, 8) -> (-86.5, 8)
  line L13 (-86.5, 8) -> (-86.5, 12)
  line L14 (-44, 0) -> (-44, 60) construction
  line L15 (-1.5, 52) -> (-4, 52)
  line L16 (-1.5, 48) -> (-1.5, 52)
  line L17 (-4, 48) -> (-1.5, 48)
  line L18 (-4, 52) -> (-4, 48)
  line L19 (-1.5, 12) -> (-4, 12)
  line L20 (-1.5, 8) -> (-1.5, 12)
  line L21 (-4, 8) -> (-1.5, 8)
  line L22 (-4, 12) -> (-4, 8)
  dimension "d76" = 2.5
  dimension "d77" = 4
  dimension "d78" = 8
  dimension "d79" = 1.5
  dimension "d80" = 2.5
  dimension "d81" = 4
  dimension "d82" = 8
  dimension "d83" = 1.5
  constraint horizontal L6
  constraint vertical L7
  constraint horizontal L8
  constraint vertical L9
  constraint horizontal L10
  constraint vertical L11
  constraint horizontal L12
  constraint vertical L13
  constraint midpoint L2 L14.start
  constraint perpendicular L2 L14
  constraint symmetric L6.start L14 L15.start
  constraint symmetric L6.end L14 L15.end
  constraint symmetric L7.end L14 L17.start
  constraint symmetric L8.end L14 L16.start
  constraint symmetric L10.start L14 L19.start
  constraint symmetric L10.end L14 L19.end
  constraint symmetric L11.end L14 L21.start
  constraint symmetric L12.end L14 L20.start
  measures "d76" distance of L6.start L6.end
  measures "d77" distance of L6.start L8.end
  measures "d78" vertical distance of L0.end L6.end
  measures "d79" distance of L1 L9
  measures "d80" distance of L10.start L10.end
  measures "d81" distance of L10.start L12.end
  measures "d82" vertical distance of A1.end L11.end
  measures "d83" distance of L1 L12.end
extrude "Extrude14" cut sketch "Sketch13" against normal blind 5 contours L6 L7 L8 L9 | L10 L11 L12 L13 | L15 L16 L17 L18 | L19 L20 L21 L22
equation "d59 = ( ( 45 + 33 ) / 2 ) * 1 mm"

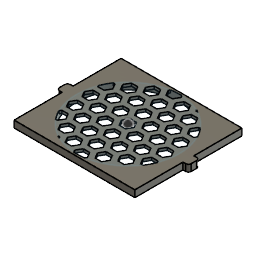
design "SleepHelperTop"
part number: 2026-09-24-13-58-19-772
Autodesk Fusion 360 part; units mm, degrees
sketch "Sketch1" plane through (0, 0, 0) normal (0, 1, 0) x (1, 0, 0)
  line L0 (0, 0) -> (88, 0)
  line L1 (88, 0) -> (88, 78)
  line L2 (88, 78) -> (0, 78)
  line L3 (0, 78) -> (0, 0)
  line L4 (0, 35) -> (-4, 35)
  line L5 (-4, 35) -> (-4, 43)
  line L6 (-4, 43) -> (0, 43)
  line L7 (0, 43) -> (0, 35)
  line L8 (88, 35) -> (92, 35)
  line L9 (92, 35) -> (92, 43)
  line L10 (92, 43) -> (88, 43)
  line L11 (88, 43) -> (88, 35)
  dimension "d1" = 88
  dimension "d2" = 78
  dimension "d3" = 8
  dimension "d4" = 35
  dimension "d5" = 4
  dimension "d6" = 8
  dimension "d9" = 35
  dimension "d10" = 4
  constraint horizontal L0
  constraint vertical L1
  constraint horizontal L2
  constraint vertical L3
  constraint coincident L0.start L3.end
  constraint horizontal L4
  constraint vertical L5
  constraint horizontal L6
  constraint vertical L7
  constraint horizontal L8
  constraint vertical L9
  constraint horizontal L10
  constraint vertical L11
  constraint coincident L1 L8.start
  measures "d1" distance of L0.start L0.end
  measures "d2" distance of L0.start L2.end
  measures "d3" distance of L4.start L6.end
  measures "d4" vertical distance of L0.start L4.end
  measures "d5" distance of L8.start L8.end
  measures "d6" distance of L8.start L10.end
  measures "d9" distance of L0.end L8
  measures "d10" distance of L4.start L4.end
extrude "Extrude1" add sketch "Sketch1" along normal blind 5 makes body 1
sketch "Sketch2" plane through (0, 5, 0) normal (0, 1, 0) x (-1, 0, 0)
  line L0 (0, -35) -> (0, 0)
  line L1 (0, 0) -> (-88, 0)
  line L2 (-88, 0) -> (-88, -35)
  line L3 (-88, -35) -> (-92, -35)
  line L4 (-92, -35) -> (-92, -43)
  line L5 (-92, -43) -> (-88, -43)
  line L6 (-88, -43) -> (-88, -78)
  line L7 (-88, -78) -> (0, -78)
  line L8 (0, -78) -> (0, -43)
  line L9 (0, -43) -> (4, -43)
  line L10 (4, -43) -> (4, -35)
  line L11 (4, -35) -> (0, -35)
  line L12 (-44, -78) -> (-44, 0) construction
  line L13 (-44, -39) -> (-92, -39) construction
  circle A0 centre (-44, -39) radius 37.5
  dimension "d11" = 75
  constraint midpoint L7 L12.start
  constraint midpoint L1 L12.end
  constraint midpoint L12 L13.start
  constraint midpoint L4 L13.end
  constraint coincident L13.start A0.centre
  measures "d11" diameter of A0
extrude "Extrude2" cut sketch "Sketch2" against normal blind 10 contours A0 bodies 1
fillet "Fillet1" radius 2 4 edges at (92, 2.5, -35) (92, 2.5, -43) (-4, 2.5, -43) (-4, 2.5, -35) on bodies 1
sketch "Sketch3" plane through (0, 5, 0) normal (0, 1, 0) x (-1, 0, 0)
  arc A0 (4, -37) -> (2, -35) centre (2, -37) ccw
  line L0 (2, -35) -> (0, -35)
  line L1 (0, -35) -> (0, 0)
  line L2 (0, 0) -> (-88, 0)
  line L3 (-88, 0) -> (-88, -35)
  line L4 (-88, -35) -> (-90, -35)
  arc A1 (-90, -35) -> (-92, -37) centre (-90, -37) ccw
  line L5 (-92, -37) -> (-92, -41)
  arc A2 (-92, -41) -> (-90, -43) centre (-90, -41) ccw
  line L6 (-90, -43) -> (-88, -43)
  line L7 (-88, -43) -> (-88, -78)
  line L8 (-88, -78) -> (0, -78)
  line L9 (0, -78) -> (0, -43)
  line L10 (0, -43) -> (2, -43)
  arc A3 (2, -43) -> (4, -41) centre (2, -41) ccw
  line L11 (4, -41) -> (4, -37)
  circle A4 centre (-44, -39) radius 37.5
  line L12 (-44, 0) -> (-44, -78) construction
  line L13 (-92, -39) -> (4, -39) construction
  constraint midpoint L2 L12.start
  constraint midpoint L8 L12.end
  constraint midpoint L5 L13.start
  constraint midpoint L11 L13.end
sketch "Sketch4" plane through (0, 0, 0) normal (0, 1, 0) x (1, 0, 0)
  line L0 (48.4086, 39.092) -> (46.0992, 43.092)
  line L1 (46.0992, 43.092) -> (41.4804, 43.092)
  line L2 (41.4804, 43.092) -> (39.171, 39.092)
  line L3 (39.171, 39.092) -> (41.4804, 35.092)
  line L4 (41.4804, 35.092) -> (46.0992, 35.092)
  line L5 (46.0992, 35.092) -> (48.4086, 39.092)
  line L6 (43.7898, 39.092) -> (43.7898, 43.092) construction
  line L7 (43.7898, 39.092) -> (47.2539, 41.092) construction
  point P0 (92, 39)
  point P1 (44, 78)
  point P2 (43.7898, 39.092)
  dimension "d19" = 8
  constraint horizontal L1
  constraint coincident P2 L6.start
  constraint midpoint L1 L6.end
  constraint midpoint L0 L7.end
  measures "d19" distance of L1 L4
sketch "Sketch5" plane through (0, 0, 0) normal (0, 1, 0) x (1, 0, 0)
extrude "Extrude3" add sketch "Sketch3" against normal blind 2 separate body contours A4 makes body 2
extrude "Extrude4" cut sketch "Sketch4" along normal blind 12 bodies 2
sketch "Sketch6" plane through (0, 5, 0) normal (0, 1, 0) x (-1, 0, 0)
  line L0 (-46.0992, -35.092) -> (-41.4804, -35.092)
  line L1 (-41.4804, -35.092) -> (-39.171, -39.092)
  line L2 (-39.171, -39.092) -> (-41.4804, -43.092)
  line L3 (-41.4804, -43.092) -> (-46.0992, -43.092)
  line L4 (-46.0992, -43.092) -> (-48.4086, -39.092)
  line L5 (-48.4086, -39.092) -> (-46.0992, -35.092)
  circle A0 centre (-44, -39) radius 37.5
  line L6 (-44, -39) -> (-43.7898, -43.092) construction
  line L7 (-44, -39) -> (-47.2539, -41.092) construction
  constraint coincident A0.centre L6.start
  constraint midpoint L3 L6.end
  constraint midpoint L4 L7.end
pattern_linear "R-Pattern1" count 7 spacing 12 along (-0.051305, 0, -0.998683) both ways count 7 spacing 12 along (0.841157, 0, -0.540791) both ways of "Extrude4"
combine "Combine1" operation add target body 1 tool bodies 2
equation "d4 = ( ( 78 - 8 ) / 2 ) * 1 mm"

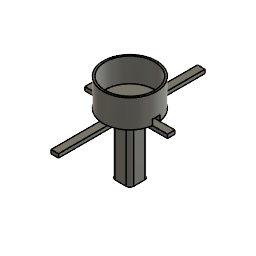
design "V2MotorDC"
part number: 2026-09-10-11-38-15-186
Autodesk Fusion 360 part; units mm, degrees
sketch "Sketch1" plane through (0, 0, 0) normal (0, 1, 0) x (1, 0, 0)
  line L0 (-22, 2) -> (22, 2)
  line L1 (22, 2) -> (22, -2)
  line L2 (22, -2) -> (-22, -2)
  line L3 (-22, -2) -> (-22, 2)
  line L4 (-2, 38) -> (2, 38)
  line L5 (2, 38) -> (2, -40)
  line L6 (2, -40) -> (-2, -40)
  line L7 (-2, -40) -> (-2, 38)
  dimension "d1" = 44
  dimension "d2" = 4
  dimension "d3" = 22
  dimension "d4" = 4
  dimension "d5" = 78
  dimension "d8" = 2
  dimension "d9" = 2
  dimension "d25" = 38
  constraint horizontal L0
  constraint vertical L1
  constraint horizontal L2
  constraint vertical L3
  constraint horizontal L4
  constraint vertical L5
  constraint horizontal L6
  constraint vertical L7
  measures "d1" distance of L0.start L0.end
  measures "d2" distance of L0.start L2.end
  measures "d3" horizontal distance of origin L1.end
  measures "d4" distance of L4.start L4.end
  measures "d5" distance of L4.start L6.end
  measures "d8" distance of origin L0
  measures "d9" distance of origin L7
  measures "d25" distance of L2 L6
extrude "Extrude1" add sketch "Sketch1" along normal blind 2 makes body 1
sketch "Sketch2" plane through (0, 2, 0) normal (0, 1, 0) x (-1, 0, 0)
  line L0 (2, 40) -> (-2, 40)
  line L1 (-2, 40) -> (-2, 2)
  line L2 (-2, 2) -> (-22, 2)
  line L3 (-22, 2) -> (-22, -2)
  line L4 (-22, -2) -> (-2, -2)
  line L5 (-2, -2) -> (-2, -38)
  line L6 (-2, -38) -> (2, -38)
  line L7 (2, -38) -> (2, -2)
  line L8 (2, -2) -> (22, -2)
  line L9 (22, -2) -> (22, 2)
  line L10 (22, 2) -> (2, 2)
  line L11 (2, 2) -> (2, 40)
  circle A0 centre (0, 0) radius 14.15
  dimension "d12" = 28.3
  constraint coincident A0.centre origin
  measures "d12" diameter of A0
extrude "Extrude2" add sketch "Sketch2" along normal blind 14.8 contours L10 L11 A0 | L1 L2 L4 L5 L7 L8 L10 L11 A0 | L1 L2 A0 | L4 L5 A0 | L7 L8 A0 bodies 1
sketch "Sketch3" plane through (0, 16.8, 0) normal (0, 1, 0) x (-1, 0, 0)
  circle A0 centre (0, 0) radius 14.15
  circle A1 centre (0, 0) radius 13.15
  dimension "d15" = -1
extrude "Extrude3" cut sketch "Sketch3" against normal blind 12.8 contours A1 bodies 1
sketch "Sketch4" plane through (0, 0, 0) normal (1, 0, 0) x (0, 0, -1)
  line L0 (2, 2) -> (-2, 2)
  line L1 (-2, 2) -> (-2, 5)
  line L2 (-2, 5) -> (2, 5)
  line L3 (2, 5) -> (2, 2)
  constraint horizontal L0
  constraint vertical L1
  constraint horizontal L2
  constraint vertical L3
extrude "Extrude4" cut sketch "Sketch4" along normal blind 32 bodies 1
move_body "Move1" bodies 1 to x (1, 0, 0) y (0, 1, 0) z (0, 0, 1) at (0, 30, 0)
sketch "Sketch5" plane through (0, 30, 0) normal (0, -1, 0) x (1, 0, 0)
  line L0 (2, 40) -> (-2, 40)
  line L1 (-2, 40) -> (-2, 2)
  line L2 (-2, 2) -> (-22, 2)
  line L3 (-22, 2) -> (-22, -2)
  line L4 (-22, -2) -> (-2, -2)
  line L5 (-2, -2) -> (-2, -38)
  line L6 (-2, -38) -> (2, -38)
  line L7 (2, -38) -> (2, -2)
  line L8 (2, -2) -> (22, -2)
  line L9 (22, -2) -> (22, 2)
  line L10 (22, 2) -> (2, 2)
  line L11 (2, 2) -> (2, 40)
  line L12 (-5, 5) -> (5, 5)
  line L13 (5, 5) -> (5, -5)
  line L14 (5, -5) -> (-5, -5)
  line L15 (-5, -5) -> (-5, 5)
  constraint horizontal L12
  constraint vertical L13
  constraint horizontal L14
  constraint vertical L15
extrude "Extrude5" add sketch "Sketch5" along normal blind 30 separate body contours L10 L11 L12 L13 | L1 L2 L4 L5 L7 L8 L10 L11 L12 L13 L14 L15 | L1 L2 L12 L15 | L7 L8 L13 L14 | L4 L5 L14 L15 makes body 2
fillet "Fillet1" radius 2 4 edges at (5, 15, 5) (-5, 15, 5) (5, 15, -5) (-5, 15, -5) on bodies 2
combine "Combine1" operation add target body 1 tool bodies 2
equation "d3 = ( 44 / 2 ) * 1 mm"
equation "d12 = 24.3 mm + 4 mm"
equation "d13 = 12.8 mm + 2 mm"
